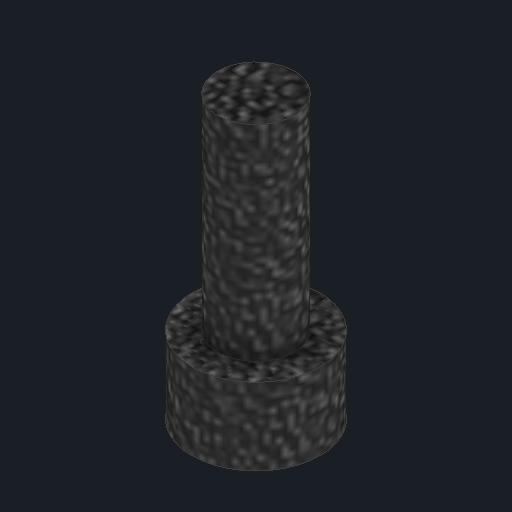
# Autodesk Inventor part: c8n_m6_shcs_16
Saved by Autodesk Inventor 2027.1 (Build 311270010, 270A)
## iProperties
Created: 2026-11-04
Part Number: c8n_m6_shcs_16
Material: Generic
Description: M6x16 cap screw, dovetail bar to tube ring (x2)
Document SubType Name: Modeling
Designer: Claude (from photos)
Density: 1 g/cm^3
Appearance: Black Cast
Author: alexg
Autodesk Inventor part; units mm, degrees
ref_plane "Work Plane1" through (0, -145, 0) normal (0, 1, 0) x (-1, 0, 0)
sketch "Head sketch" plane through (0, -145, 0) normal (0, 1, 0) x (-1, 0, 0)
  circle A0 centre (0, 0) radius 5
  constraints: 1 centre point
extrude "Head" add sketch "Head sketch" along normal blind 6
ref_plane "Work Plane2" through (0, -145, 0) normal (0, 1, 0) x (-1, 0, 0)
sketch "Hex socket sketch" plane through (0, -145, 0) normal (0, 1, 0) x (-1, 0, 0)
  line L0 (-2.8868, 0) -> (-1.4434, 2.5)
  line L1 (-1.4434, 2.5) -> (1.4434, 2.5)
  line L2 (1.4434, 2.5) -> (2.8868, 0)
  line L3 (2.8868, 0) -> (1.4434, -2.5)
  line L4 (1.4434, -2.5) -> (-1.4434, -2.5)
  line L5 (-1.4434, -2.5) -> (-2.8868, 0)
  constraints: 12 end point
extrude "Hex socket" cut sketch "Hex socket sketch" along normal blind 3
ref_plane "Work Plane3" through (0, -139, 0) normal (0, 1, 0) x (-1, 0, 0)
sketch "Shank sketch" plane through (0, -139, 0) normal (0, 1, 0) x (-1, 0, 0)
  circle A0 centre (0, 0) radius 3
  constraints: 1 centre point
extrude "Shank" add sketch "Shank sketch" along normal blind 16
body "Solid1"
